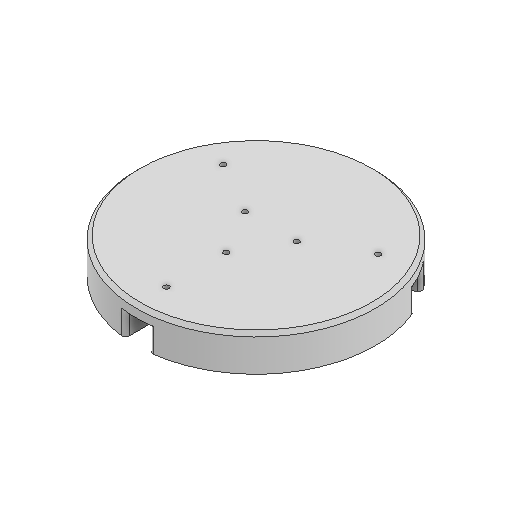
# Autodesk Inventor part: 3DP_PLA_A_Axis_Bearing_Base_Stand_Bottom_Plate_REVB
Saved by Autodesk Inventor 2027 (Build 310192060, 192F)
## iProperties
Created: 2026-01-18
Part Number: 3DP_PLA_A_Axis_Bearing_Base_Stand_Bottom_Plate_REVB
Material: Generic
Document SubType Name: Modeling
Designer: Andrzej
Density: 1 g/cm^3
Appearance: Default
Author: Andrzej
Autodesk Inventor part; units mm, degrees
ref_plane "YZ Plane" through (0, 0, 0) normal (1, 0, 0) x (0, 1, 0)
ref_plane "XZ Plane" through (0, 0, 0) normal (0, 1, 0) x (-1, 0, 0)
ref_plane "XY Plane" through (0, 0, 0) normal (0, 0, 1) x (1, 0, 0)
sketch "Sketch5" plane through (0, 0, 0) normal (0, 1, 0) x (-1, 0, 0)
  circle A0 centre (0, 0) radius 100.1
  line L0 (-10.1, 99.5892) -> (-10.1, 0)
  line L1 (10.1, 99.5892) -> (10.1, 0)
  line L2 (-91.2967, -41.0477) -> (-5.05, 8.7469)
  line L3 (-81.1967, -58.5414) -> (5.05, -8.7469)
  line L4 (81.1967, -58.5414) -> (-5.05, -8.7469)
  line L5 (91.2967, -41.0477) -> (5.05, 8.7469)
  line L6 (10.1, 5.8312) -> (0, -11.6625)
  line L7 (0, -11.6625) -> (-10.1, 5.8312)
  line L8 (-10.1, 5.8312) -> (10.1, 5.8312)
  line L9 (-41.5115, -82.6622) -> (0, 0)
  line L10 (0, 0) -> (0, -118) construction
  line L11 (41.5163, -82.6598) -> (0, 0)
  point P0 (91.0952, -16.0598)
  point P1 (67.2802, 63.4793)
  point P2 (-91.0942, -16.0651)
  point P3 (-67.2839, 63.4754)
  point P4 (10.7359, 91.8749)
  point P5 (-10.25, 5.9178)
  point P6 (81.1967, -58.5414)
  point P7 (0, -11.8357)
  point P8 (-81.1967, -58.5414)
  point P9 (10.25, 5.9178)
  point P10 (91.2967, -41.0477)
  dimension "d62" = 200.2
  dimension "d63" = 20.2
  dimension "d64" = 10.1
  dimension "d67" = 360
  dimension "d69" = 92.5
  dimension "d72" = 160
  dimension "d76" = 160
  dimension "d96" = 26.665
  constraints: 24 end point, 6 point on line, 3 vertical, 2 horizontal alignment, 2 point on circle, 1 centre point, 1 coincident, 27 other
  measures "d62" diameter of A0
  measures "d63" distance between parallel lines of L1 L0
  measures "d64" distance from line of L1 point (0, 0)
  measures "d69" distance of point (0, 0) L9.start
  measures "d96" angle of L9 L10
extrude "Extrusion4" add sketch "Sketch5" along normal blind 10
extrude "Extrusion5" add sketch "Sketch5" against normal blind 20 contours A0 L5 L1 | L0 L2 A0 | A0 L3 L4
sketch "Sketch10" plane through (0, 0, 0) normal (0, -1, 0) x (1, 0, 0)
  point P0 (0, 0)
  point P1 (0, 25)
  point P2 (0, 75)
  dimension "d122" = 25
  dimension "d133" = 75
  constraints: 2 vertical alignment
  measures "d122" distance of point (0, 0) point (0, 25)
  measures "d133" distance of point (0, 0) point (0, 75)
hole "Hole7" at (0, 0, 25) at (0, 0, 75) direction (0, 1, 0) diameter 4.5 end through all
pattern_circular "Circular Pattern2" count 3 over 360 about axis through (0, 0, 0) along (0, 1, 0) of "Hole7"
sketch "Sketch11" plane through (0, -20, 0) normal (0, -1, 0) x (1, 0, 0)
  arc A0 (-10.1, 99.5892) -> (-91.2967, -41.0477) centre (0, 0) ccw projected
  line L0 (-91.2967, -41.0477) -> (-10.1, 5.8312) projected
  line L1 (-10.1, 5.8312) -> (-10.1, 99.5892) projected
  arc A1 (-25.1, 81.3142) -> (-82.9702, -18.9199) centre (0, 0) ccw
  line L2 (-82.9702, -18.9199) -> (-25.1, 14.4915)
  line L3 (-25.1, 14.4915) -> (-25.1, 81.3142)
  dimension "d134" = 15
  constraints: 4 end point, 2 point on circle, 1 centre point, 2 other
  measures "d134" distance between parallel lines of L1 L3
extrude "Extrusion8" cut sketch "Sketch11" against normal blind 20 contours L3 L2 A1
fillet "Fillet2" radius 5 3 edges at (-25.1, -10, 81.3142) (-25.1, -10, 14.4915) (-82.9702, -10, -18.9199)
pattern_circular "Circular Pattern3" count 3 over 360 about axis through (0, 0, 0) along (0, 1, 0) of "Fillet2", "Extrusion8"
fillet "Fillet3" radius 3 6 edges at (-81.1967, -10, -58.5414) (-91.2967, -10, -41.0477) (81.1967, -10, -58.5414) (91.2967, -10, -41.0477) (-10.1, -10, 99.5892) (10.1, -10, 99.5892)
chamfer "Chamfer4" distance 3 angle 45 1 edges at (100.1, 10, 0)
equation "\"d64\" = 0.5 * d63"
body "Solid2"
